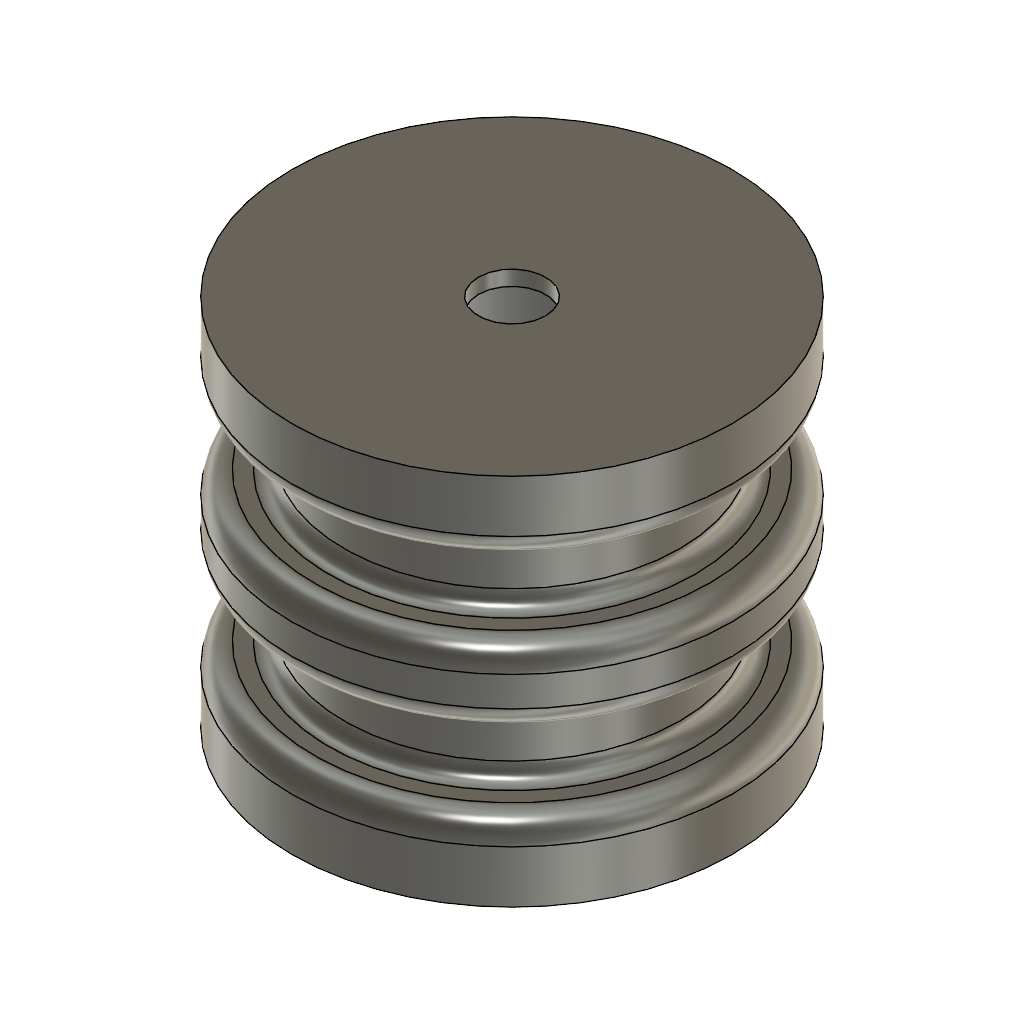
dampener 25.25 (Autodesk Fusion 360 design; units mm, degrees)
part number: 2026-10-13-17-42-59-038
Autodesk Fusion 360 part; units mm, degrees
sketch "Sketch1" plane through (0, 0, 0) normal (0, 1, 0) x (1, 0, 0)
  line L0 (0, 0) -> (0, -25)
  line L1 (0, -25) -> (2.25, -25)
  line L2 (2.25, -25) -> (2.25, 0)
  line L3 (2.25, 0) -> (0, 0)
  line L4 (0, 0) -> (0, -25)
  line L5 (2.25, 0) -> (14.75, 0)
  line L6 (12.25, -5) -> (13.25, -5)
  line L7 (12.25, -10) -> (13.25, -10)
  line L8 (12.25, -15) -> (13.25, -15)
  line L9 (12.25, -20) -> (13.25, -20)
  line L10 (2.25, -25) -> (14.75, -25)
  line L11 (14.75, -25) -> (14.75, -21.5)
  line L12 (14.75, -13.5) -> (14.75, -11.5)
  line L13 (14.75, -3.5) -> (14.75, 0)
  line L14 (11.25, -19) -> (11.25, -16)
  line L15 (11.25, -9) -> (11.25, -6)
  arc A0 (11.25, -19) -> (12.25, -20) centre (12.25, -19) ccw
  arc A1 (12.25, -15) -> (11.25, -16) centre (12.25, -16) ccw
  arc A2 (11.25, -9) -> (12.25, -10) centre (12.25, -9) ccw
  arc A3 (12.25, -5) -> (11.25, -6) centre (12.25, -6) ccw
  arc A4 (14.75, -21.5) -> (13.25, -20) centre (13.25, -21.5) ccw
  arc A5 (13.25, -15) -> (14.75, -13.5) centre (13.25, -13.5) ccw
  arc A6 (13.25, -5) -> (14.75, -3.5) centre (13.25, -3.5) ccw
  arc A7 (14.75, -11.5) -> (13.25, -10) centre (13.25, -11.5) ccw
  line L16 (2.25, -24) -> (13.75, -24)
  line L17 (13.75, -24) -> (13.75, -21.5)
  arc A8 (13.75, -21.5) -> (13.25, -21) centre (13.25, -21.5) ccw
  line L18 (12.25, -21) -> (13.25, -21)
  arc A9 (10.25, -19) -> (12.25, -21) centre (12.25, -19) ccw
  line L19 (10.25, -19) -> (10.25, -16)
  arc A10 (12.25, -14) -> (10.25, -16) centre (12.25, -16) ccw
  line L20 (12.25, -14) -> (13.25, -14)
  arc A11 (13.25, -14) -> (13.75, -13.5) centre (13.25, -13.5) ccw
  line L21 (13.75, -13.5) -> (13.75, -11.5)
  arc A12 (13.75, -11.5) -> (13.25, -11) centre (13.25, -11.5) ccw
  line L22 (12.25, -11) -> (13.25, -11)
  arc A13 (10.25, -9) -> (12.25, -11) centre (12.25, -9) ccw
  line L23 (10.25, -9) -> (10.25, -6)
  arc A14 (12.25, -4) -> (10.25, -6) centre (12.25, -6) ccw
  line L24 (12.25, -4) -> (13.25, -4)
  arc A15 (13.25, -4) -> (13.75, -3.5) centre (13.25, -3.5) ccw
  line L25 (13.75, -3.5) -> (13.75, -1)
  line L26 (2.25, -1) -> (13.75, -1)
  dimension "d2" = 2.25
  dimension "d3" = 25
  dimension "d4" = 12.5
  dimension "d14" = 1
  dimension "d15" = 1.5
  dimension "d16" = -1
  constraint coincident L0.start L3.end
  constraint vertical L0
  constraint horizontal L1
  constraint vertical L2
  constraint horizontal L3
  constraint vertical L4
  constraint perpendicular L2 L5
  constraint perpendicular L8 L14
  constraint tangent L14 A0
  constraint tangent L9 A0
  constraint tangent L14 A1
  constraint tangent L8 A1
  constraint equal A0 A1
  constraint tangent L15 A2
  constraint tangent L7 A2
  constraint equal A0 A2
  constraint tangent L15 A3
  constraint tangent L6 A3
  constraint equal A0 A3
  constraint tangent L9 A4
  constraint tangent L11 A4
  constraint tangent L8 A5
  constraint tangent L12 A5
  constraint equal A4 A5
  constraint tangent L6 A6
  constraint tangent L13 A6
  constraint equal A4 A6
  constraint tangent L7 A7
  constraint tangent L12 A7
  constraint equal A4 A7
  measures "d2" distance of L0.end L1.end
  measures "d3" distance of L0.end L0.start
  measures "d4" distance of L2.end L5.end
  measures "d14" radius of A0
  measures "d15" radius of A4
revolve "Revolve1" add sketch "Sketch1" angle 360 about axis through (0, 0, 0) along (0, 0, 1) contours L2 L5 L6 L7 L8 L9 L10 L11 L12 L13 L14 L15 A0 A1 A2 A3 A4 A5 A6 A7 L16 L17 A8 L18 A9 L19 A10 L20 A11 L21 A12 L22 A13 L23 A14 L24 A15 L25 L26
equation "d4 = ( 25 / 2 ) * 1 mm"
